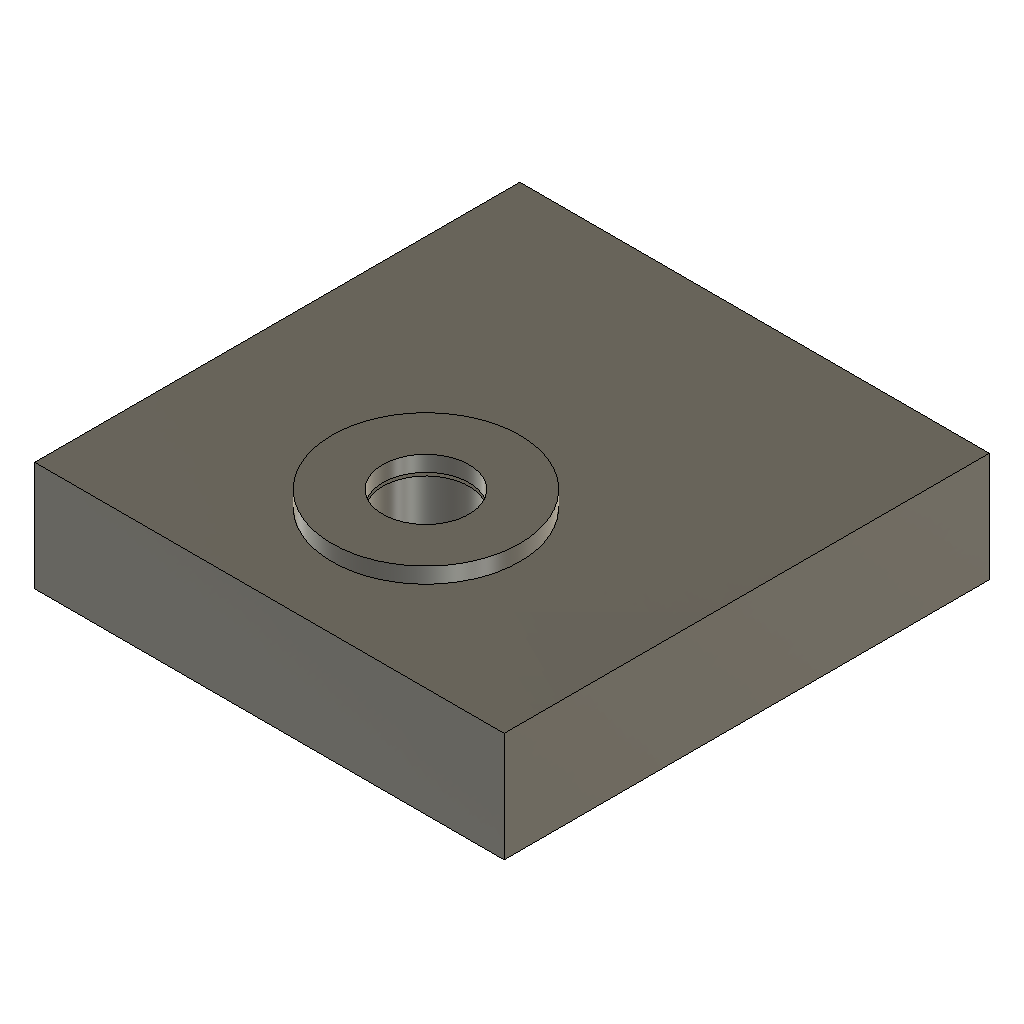
metal-clamp-study (Autodesk Fusion 360 design; units mm, degrees)
part number: 2026-10-31-10-05-39-005
part number: 2026-10-31-10-05-39-326
part number: 2026-10-31-10-05-39-583
part number: 2026-10-31-10-05-40-110
Autodesk Fusion 360 part; units mm, degrees
ref_plane "WorkPlane1" through (0, 0, 15) normal (0, 0, 1) x (1, 0, 0) in component "PRINT clamp coupon"
sketch "Carrier clamp test block sketch" plane through (0, 0, 15) normal (0, 0, 1) x (1, 0, 0) in component "PRINT clamp coupon"
  line L0 (0, 0) -> (30, 0)
  line L1 (30, 0) -> (30, 31)
  line L2 (30, 31) -> (0, 31)
  line L3 (0, 31) -> (0, 0)
  dimension "d70" = 30
  dimension "d71" = 31
  constraint horizontal L0
  constraint vertical L1
  constraint horizontal L2
  constraint vertical L3
  constraint vertical L0.start L3.end
  constraint horizontal L0.start L3.end
  measures "d70" horizontal distance of L0.start L0.end
  measures "d71" vertical distance of L0.end L1.end
extrude "Carrier clamp test block" add sketch "Carrier clamp test block sketch" along normal blind 7 makes body 1 in component "PRINT clamp coupon"
ref_plane "WorkPlane2" through (0, 0, 15) normal (0, 0, 1) x (1, 0, 0) in component "PRINT clamp coupon"
sketch "Metal sleeve bore sketch" plane through (0, 0, 15) normal (0, 0, 1) x (1, 0, 0) in component "PRINT clamp coupon"
  circle A0 centre (15, 10) radius 4.1
  dimension "d76" = 15
  dimension "d77" = 10
  dimension "d78" = 8.2
  measures "d76" horizontal distance of origin A0.centre
  measures "d77" vertical distance of origin A0.centre
  measures "d78" diameter of A0
extrude "Metal sleeve bore" cut sketch "Metal sleeve bore sketch" along normal blind 7 bodies 1 in component "PRINT clamp coupon"
ref_plane "WorkPlane3" through (0, 0, 15) normal (0, 0, 1) x (1, 0, 0) in component "PRINT clamp coupon"
sketch "Front flange bearing counterbore sketch" plane through (0, 0, 15) normal (0, 0, 1) x (1, 0, 0) in component "PRINT clamp coupon"
  circle A0 centre (15, 10) radius 6.1
  dimension "d83" = 15
  dimension "d84" = 10
  dimension "d85" = 12.2
  measures "d83" horizontal distance of origin A0.centre
  measures "d84" vertical distance of origin A0.centre
  measures "d85" diameter of A0
extrude "Front flange bearing counterbore" cut sketch "Front flange bearing counterbore sketch" along normal blind 3 bodies 1 in component "PRINT clamp coupon"
ref_plane "WorkPlane1" through (0, 0, 15) normal (0, 0, 1) x (1, 0, 0) in component "CUSTOM METAL flanged countersunk limiter"
sketch "Broad front flange sketch" plane through (0, 0, 15) normal (0, 0, 1) x (1, 0, 0) in component "CUSTOM METAL flanged countersunk limiter"
  circle A0 centre (15, 10) radius 6
  dimension "d90" = 15
  dimension "d91" = 10
  dimension "d92" = 12
  measures "d90" horizontal distance of origin A0.centre
  measures "d91" vertical distance of origin A0.centre
  measures "d92" diameter of A0
extrude "Broad front flange" add sketch "Broad front flange sketch" along normal blind 3 separate body makes body 2 in component "CUSTOM METAL flanged countersunk limiter"
ref_plane "WorkPlane2" through (0, 0, 18) normal (0, 0, 1) x (1, 0, 0) in component "CUSTOM METAL flanged countersunk limiter"
sketch "Compression sleeve sketch" plane through (0, 0, 18) normal (0, 0, 1) x (1, 0, 0) in component "CUSTOM METAL flanged countersunk limiter"
  circle A0 centre (15, 10) radius 4
  dimension "d97" = 15
  dimension "d98" = 10
  dimension "d99" = 8
  measures "d97" horizontal distance of origin A0.centre
  measures "d98" vertical distance of origin A0.centre
  measures "d99" diameter of A0
extrude "Compression sleeve" add sketch "Compression sleeve sketch" along normal blind 3.8 bodies 2 in component "CUSTOM METAL flanged countersunk limiter"
ref_plane "WorkPlane3" through (0, 0, 15) normal (0, 0, 1) x (1, 0, 0) in component "CUSTOM METAL flanged countersunk limiter"
sketch "M5 passage sketch" plane through (0, 0, 15) normal (0, 0, 1) x (1, 0, 0) in component "CUSTOM METAL flanged countersunk limiter"
  circle A0 centre (15, 10) radius 2.75
  dimension "d104" = 15
  dimension "d105" = 10
  dimension "d106" = 5.5
  measures "d104" horizontal distance of origin A0.centre
  measures "d105" vertical distance of origin A0.centre
  measures "d106" diameter of A0
extrude "M5 passage" cut sketch "M5 passage sketch" along normal blind 7 bodies 2 in component "CUSTOM METAL flanged countersunk limiter"
ref_plane "WorkPlane4" through (0, 0, 15) normal (0, 0, 1) x (1, 0, 0) in component "CUSTOM METAL flanged countersunk limiter"
sketch "M5 countersunk metal seat sketch" plane through (0, 0, 15) normal (0, 0, 1) x (1, 0, 0) in component "CUSTOM METAL flanged countersunk limiter"
  circle A0 centre (15, 10) radius 4.7
  dimension "d111" = 15
  dimension "d112" = 10
  dimension "d113" = 9.4
  measures "d111" horizontal distance of origin A0.centre
  measures "d112" vertical distance of origin A0.centre
  measures "d113" diameter of A0
extrude "M5 countersunk metal seat" cut sketch "M5 countersunk metal seat sketch" along normal blind 1.95 draft -45 bodies 2 in component "CUSTOM METAL flanged countersunk limiter"
ref_plane "WorkPlane1" through (0, 0, 22) normal (0, 0, 1) x (1, 0, 0) in component "METAL rear spreader washer 12x5.5x1"
sketch "Washer bridging profile mouth sketch" plane through (0, 0, 22) normal (0, 0, 1) x (1, 0, 0) in component "METAL rear spreader washer 12x5.5x1"
  circle A0 centre (15, 10) radius 6
  dimension "d118" = 15
  dimension "d119" = 10
  dimension "d120" = 12
  measures "d118" horizontal distance of origin A0.centre
  measures "d119" vertical distance of origin A0.centre
  measures "d120" diameter of A0
extrude "Washer bridging profile mouth" add sketch "Washer bridging profile mouth sketch" along normal blind 1 separate body makes body 3 in component "METAL rear spreader washer 12x5.5x1"
ref_plane "WorkPlane2" through (0, 0, 22) normal (0, 0, 1) x (1, 0, 0) in component "METAL rear spreader washer 12x5.5x1"
sketch "Washer clearance sketch" plane through (0, 0, 22) normal (0, 0, 1) x (1, 0, 0) in component "METAL rear spreader washer 12x5.5x1"
  circle A0 centre (15, 10) radius 2.75
  dimension "d125" = 15
  dimension "d126" = 10
  dimension "d127" = 5.5
  measures "d125" horizontal distance of origin A0.centre
  measures "d126" vertical distance of origin A0.centre
  measures "d127" diameter of A0
extrude "Washer clearance" cut sketch "Washer clearance sketch" along normal blind 1 bodies 3 in component "METAL rear spreader washer 12x5.5x1"
component "PRINT clamp coupon" placed x (1, 0, 0) y (0, 1, 0) z (0, 0, 1) at (0, 0, 0)
component "CUSTOM METAL flanged countersunk limiter" placed x (1, 0, 0) y (0, 1, 0) z (0, 0, 1) at (0, 0, 0)
component "METAL rear spreader washer 12x5.5x1" placed x (1, 0, 0) y (0, 1, 0) z (0, 0, 1) at (0, 0, 0)
equation "columns = 12" comment "Even integer 4..14; each cell is 20 mm"
equation "rows = 12" comment "Even integer 4..14"
equation "pitch = 20 mm" comment "Keep for dense SKADIS compatible lattice"
equation "panelWidth = columns * pitch" comment "Nominal module pitch X"
equation "panelHeight = rows * pitch" comment "Nominal module pitch Y"
equation "seamGap = 0.35 mm" comment "Physical envelope shrinks around fixed lattice"
equation "boardThickness = 5 mm" comment "Fit-test with real hooks"
equation "slotWidth = 5 mm" comment "Minimum throat width"
equation "slotHeight = 15 mm" comment "Minimum throat height"
equation "entryRadius = 0.4 mm" comment "Front slot and perimeter edge rounding"
equation "cornerRadius = 6 mm" comment "Plan-view panel corner rounding"
equation "hookClearance = 10 mm" comment "PROVISIONAL unobstructed depth behind board; carriers begin at its rear boundary"
equation "frameZ = carrierZ + carrierThickness" comment "Front extrusion datum"
equation "profileMouth = 6.28 mm" comment "User measured mouth"
equation "profileCavity = 11 mm" comment "User measured widest cavity"
equation "profileDepth = 6.2 mm" comment "User measured face-to-floor depth"
equation "profileFloor = 5.7 mm" comment "User estimate, lower confidence"
equation "profileLip = 1.5 mm" comment "Unmeasured; tentative comparable catalog value"
equation "profileTaperStart = profileDepth - ( profileCavity - profileFloor ) / 2" comment "Assumed 45-degree inner slopes"
equation "profileBore = 5 mm" comment "Unmeasured central bore, reference only"
equation "nutWidth = 8.8 mm" comment "Provisional low-profile METAL T-nut envelope, not old rectangular carrier"
equation "nutLength = 12 mm" comment "End-loaded anti-rotation metal nut envelope"
equation "nutThickness = 2.7 mm" comment "Thin nut reference; fit/load still unverified"
equation "jointLeg = 18 mm" comment "In-bay angle footprint"
equation "jointThickness = 3 mm" comment "Metal bracket thickness"
equation "jointDepth = 16 mm" comment "Bracket depth within 20 mm rail"
equation "sideScrewLength = 8 mm" comment "M5x8 reference; check against actual bracket and nut"
equation "wallTabHeight = 24 mm" comment "Tab along extrusion"
equation "wallTabReach = 22 mm" comment "Tab into open bay"
equation "wallAnchorClearance = 6.5 mm" comment "Placeholder wall anchor interface"
equation "wallDriverDiameter = 12 mm" comment "Clear tool envelope in open bays"
equation "keyDriverDiameter = 5 mm" comment "Short hex-key working-leg envelope"
equation "keyDriverReach = 20 mm" comment "Short hex-key working-leg reach"
equation "supportWidth = 3.2 mm" comment "Prototype blade; two perimeter lines need print review"
equation "supportLength = 12 mm" comment "Compression bearing length"
equation "hookEnvelopeWidth = 6 mm" comment "Conservative provisional continuous hook column"
equation "carrierThickness = 7 mm" comment "Room for captive M2 nut and stock M5x12"
equation "panelClearance = 2.4 mm" comment "M2 clearance"
equation "panelHeadPocket = 4 mm" comment "DIN965 3.8 mm head plus 0.1 mm recess"
equation "carrierHeadPocket = 9.4 mm" comment "DIN965 M5 9.2 mm head plus recess"
equation "carrierBore = 5.5 mm" comment "M5 clearance"
equation "tongueWidth = 2.8 mm" comment "Rear axial registration tongue"
equation "tongueLength = 8 mm" comment "Axial release registration"
equation "tongueDepth = 0.6 mm" comment "Tongue engagement"
equation "registerClearance = 0.2 mm" comment "Each side of printed tongue"
equation "carrierZ = boardThickness + hookClearance" comment "Rear hook cavity boundary"
equation "stepCorner = 0.6 mm" comment "Small plan corner relief; printed fit remains untested"
equation "limiterGap = 0.2 mm" comment "Uncompressed axial gap; establish by material and torque trials"
equation "d76 = abs(15 mm)"
equation "d77 = abs(10 mm)"
equation "d83 = abs(15 mm)"
equation "d84 = abs(10 mm)"
equation "d90 = abs(15 mm)"
equation "d91 = abs(10 mm)"
equation "d97 = abs(15 mm)"
equation "d98 = abs(10 mm)"
equation "d100 = 4 mm - limiterGap"
equation "d104 = abs(15 mm)"
equation "d105 = abs(10 mm)"
equation "d111 = abs(15 mm)"
equation "d112 = abs(10 mm)"
equation "d118 = abs(15 mm)"
equation "d119 = abs(10 mm)"
equation "d125 = abs(15 mm)"
equation "d126 = abs(10 mm)"
